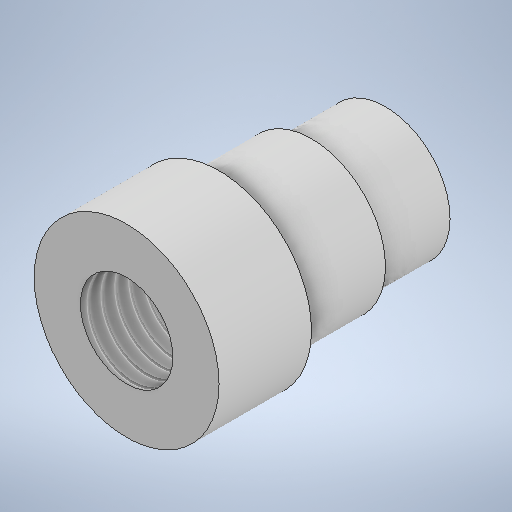
# Autodesk Inventor part: Cilindro base
Saved by Autodesk Inventor 2025.2 (Build 292293000, 293)
## iProperties
Created: 2025-03-19
Part Number: Cilindro base
Material: Generic
Document SubType Name: Modeling
Designer: laura
Density: 1 g/cm^3
Appearance: Default
Author: laura
Autodesk Inventor part; units mm, degrees
ref_plane "YZ Plane" through (0, 0, 0) normal (1, 0, 0) x (0, 1, 0)
ref_plane "XZ Plane" through (0, 0, 0) normal (0, 1, 0) x (-1, 0, 0)
ref_plane "XY Plane" through (0, 0, 0) normal (0, 0, 1) x (1, 0, 0)
sketch "Sketch1" plane through (0, 0, 0) normal (0, 1, 0) x (-1, 0, 0)
  line L0 (0, 4) -> (10, 4)
  line L1 (10, 4) -> (10, 14)
  line L2 (10, 14) -> (0, 14)
  line L3 (0, -14) -> (7, -14)
  line L4 (7, -14) -> (7, -6)
  line L5 (0, 14) -> (0, -14)
  line L6 (8, -6) -> (8, 4)
  line L7 (8, -6) -> (0, -6)
  point P0 (0, 0)
  point P1 (0, 0)
  dimension "d2" = 8
  dimension "d4" = 10
  dimension "d29" = 14
  dimension "d30" = 20
  dimension "d31" = 16
  dimension "d39" = 10
  constraints: 16 end point, 5 perpendicular, 5 point on line, 2 coincident, 2 vertical, 1 midpoint, 2 other
  measures "d2" distance of L4.end L3.end
  measures "d4" distance of L0.end L1.end
  measures "d29" diameter of L4 L5
  measures "d30" diameter of L1 L5
  measures "d31" diameter of L6 L5
  measures "d39" distance between parallel lines of L7 L0
revolve "Revolution3" add sketch "Sketch1" angle 360 about axis through (0, 0, 14) along (0, 0, -1)
sketch "Sketch2" plane through (0, 0, 14) normal (0, 0, 1) x (1, 0, 0)
  circle A0 centre (0, 0) radius 10 projected
  point P0 (0, 0)
  point P1 (0, 0)
  point P2 (0, 0)
  point P3 (0, 0)
  constraints: 6 coincident
hole "Hole1" at (0, 0, 14) direction (0, 0, -1) diameter 10 depth 10 tip angle 118
thread "Thread10" size "M10x1.5" class "6H" standard "ANSI Metric M Profile" full length
sketch "Sketch3" plane through (0, 0, -14) normal (0, 0, -1) x (-1, 0, 0)
  circle A0 centre (0, 0) radius 7 projected
  point P0 (0, 0)
  constraints: 1 coincident
hole "Hole2" at (0, 0, -14) direction (0, 0, 1) diameter 6 depth 5 tip angle 118
thread "Thread11" size "M6x1" class "6H" standard "ANSI Metric M Profile" full length
body "Solid2"
